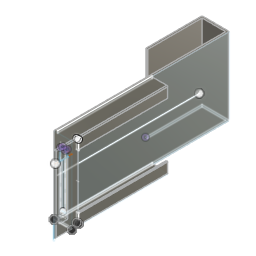
Shower Phone Caddy (Autodesk Fusion 360 design; units mm, degrees)
Autodesk Fusion 360 part; units mm, degrees
sketch "Sketch1" plane through (0, 0, 0) normal (0, 0, 1) x (1, 0, 0)
  line L0 (0, 0) -> (2, 0)
  line L1 (0, 0) -> (0, 60)
  line L2 (2, 0) -> (2, 58)
  line L3 (2, 58) -> (27, 58)
  line L4 (0, 60) -> (29, 60)
  line L5 (27, 58) -> (27, -124)
  line L6 (29, 60) -> (29, -122)
  line L7 (27, -124) -> (46, -124)
  line L8 (29, -122) -> (44, -122)
  line L9 (46, -124) -> (46, -117)
  line L10 (44, -122) -> (44, -117)
  line L11 (44, -117) -> (46, -117)
  dimension "d1" = 2
  dimension "d2" = 60
  dimension "d3" = 58
  dimension "d4" = 25
  dimension "d5" = 29
  dimension "d6" = 182
  dimension "d7" = 182
  dimension "d8" = 19
  dimension "d9" = 15
  dimension "d10" = 7
  dimension "d11" = 5
  constraint coincident L0.start L1.start
  constraint horizontal L0
  constraint perpendicular L0 L1
  constraint perpendicular L0 L2
  constraint perpendicular L2 L3
  constraint perpendicular L1 L4
  constraint perpendicular L3 L5
  constraint perpendicular L4 L6
  constraint perpendicular L5 L7
  constraint perpendicular L6 L8
  constraint perpendicular L7 L9
  constraint perpendicular L8 L10
  measures "d1" distance of L0.start L0.end
  measures "d2" distance of L0.start L1.end
  measures "d3" distance of L0.end L2.end
  measures "d4" distance of L2.end L3.end
  measures "d5" distance of L1.end L4.end
  measures "d6" distance of L3.end L5.end
  measures "d7" distance of L4.end L6.end
  measures "d8" distance of L5.end L7.end
  measures "d9" distance of L6.end L8.end
  measures "d10" distance of L7.end L9.end
  measures "d11" distance of L8.end L10.end
extrude "Extrude1" add sketch "Sketch1" along normal blind 81.5
sketch "Sketch2" plane through (29, 0, 0) normal (1, 0, 0) x (0, 1, 0)
  line L0 (-122, 0) -> (60, 0)
  line L1 (60, 0) -> (60, 81.5)
  line L2 (60, 81.5) -> (-122, 81.5)
  line L3 (-122, 81.5) -> (-122, 0)
  line L4 (-122, 0) -> (-122, 2)
  line L5 (-122, 0) -> (-22, 0)
  line L6 (-122, 2) -> (-22, 2)
  line L7 (-22, 2) -> (-22, 0)
  line L8 (-122, 40.75) -> (28, 40.75)
  line L9 (-122, 81.5) -> (-122, 79.5)
  line L10 (-122, 81.5) -> (-22, 81.5)
  line L11 (-122, 79.5) -> (-22, 79.5)
  line L12 (-22, 79.5) -> (-22, 81.5)
  dimension "d14" = 2
  dimension "d15" = 100
  dimension "d16" = 100
  dimension "d17" = 150
  constraint coincident L0.start L3.end
  constraint perpendicular L0 L4
  constraint perpendicular L3 L5
  constraint perpendicular L3 L6
  constraint midpoint L3 L8.start
  constraint perpendicular L3 L8
  constraint symmetric L0.start L8 L2.end
  constraint symmetric L4.end L8 L9.end
  constraint symmetric L5.end L8 L10.end
  constraint symmetric L6.end L8 L11.end
  measures "d14" distance of L0.start L4.end
  measures "d15" distance of L0.start L5.end
  measures "d16" distance of L4.end L6.end
  measures "d17" distance of L8.start L8.end
extrude "Extrude2" add sketch "Sketch2" along normal blind 17 contours L0 L3 L4 L5 L6 L7 | L2 L3 L9 L10 L11 L12
sketch "Sketch3" plane through (0, -117, 0) normal (0, 1, 0) x (-1, 0, 0)
  line L0 (-44, 79.5) -> (-46, 79.5)
  line L1 (-46, 79.5) -> (-46, 2)
  line L2 (-46, 2) -> (-44, 2)
  line L3 (-44, 2) -> (-44, 79.5)
  line L4 (-46, 2) -> (-46, 12)
  line L5 (-44, 2) -> (-46, 2)
  line L6 (-44, 2) -> (-44, 12)
  line L7 (-44, 12) -> (-46, 12)
  line L8 (-46, 40.75) -> (-44, 40.75) construction
  line L9 (-44, 79.5) -> (-46, 79.5)
  line L10 (-46, 79.5) -> (-46, 69.5)
  line L11 (-44, 79.5) -> (-44, 69.5)
  line L12 (-44, 69.5) -> (-46, 69.5)
  dimension "d21" = 10
  constraint coincident L1.end L2.start
  constraint perpendicular L2 L4
  constraint coincident L2.end L3.start
  constraint perpendicular L2 L6
  constraint midpoint L1 L8.start
  constraint midpoint L3 L8.end
  constraint symmetric L1.end L8 L0.end
  constraint symmetric L4.end L8 L10.end
  constraint symmetric L2.end L8 L0.start
  constraint symmetric L6.end L8 L11.end
  constraint equal L4 L6
  measures "d21" distance of L2.end L6.end
extrude "Extrude3" add sketch "Sketch3" along normal blind 95 contours L0 L1 L3 L9 L10 L11 L12 | L1 L2 L3 L4 L5 L6 L7
sketch "Sketch4" plane through (0, -124, 0) normal (0, -1, 0) x (1, 0, 0)
  line L0 (27, 0) -> (46, 0)
  line L1 (46, 0) -> (46, 81.5)
  line L2 (46, 81.5) -> (27, 81.5)
  line L3 (27, 81.5) -> (27, 0)
  line L4 (34, 74.5) -> (34, 7) construction
  line L5 (34, 7) -> (39, 7) construction
  line L6 (39, 7) -> (39, 74.5) construction
  line L7 (39, 74.5) -> (34, 74.5) construction
  line L8 (36.5, 7) -> (36.5, 12) construction
  line L9 (36.5, 74.5) -> (36.5, 69.5) construction
  line L10 (39, 69.5) -> (34, 69.5)
  line L11 (39, 12) -> (34, 12)
  line L12 (39, 69.5) -> (39, 12)
  line L13 (34, 12) -> (34, 69.5)
  dimension "d24" = -7
  dimension "d52" = 5
  constraint midpoint L5 L8.start
  constraint perpendicular L5 L8
  constraint midpoint L7 L9.start
  constraint perpendicular L7 L9
  constraint equal L8 L9
  constraint coincident L6 L10.start
  constraint coincident L4 L10.end
  constraint perpendicular L4 L10
  constraint coincident L6 L11.start
  constraint coincident L4 L11.end
  constraint perpendicular L4 L11
  measures "d52" distance of L8.start L8.end
extrude "Extrude4" cut sketch "Sketch4" against normal blind 2 contours L10 L11 L12 L13
sketch "Sketch5" plane through (0, 0, 0) normal (0, 0, -1) x (1, 0, 0)
  line L0 (46, 22) -> (46, 124)
  line L1 (46, 124) -> (27, 124)
  line L2 (27, 124) -> (27, -58)
  line L3 (27, -58) -> (2, -58)
  line L4 (2, -58) -> (2, 0)
  line L5 (2, 0) -> (0, 0)
  line L6 (0, 0) -> (0, -60)
  line L7 (0, -60) -> (29, -60)
  line L8 (29, -60) -> (29, 22)
  line L9 (29, 22) -> (46, 22)
  line L10 (27, 124) -> (46, 143)
  line L11 (46, 124) -> (46, 143)
  line L12 (46, 124) -> (27, 124)
  constraint coincident L1.end L2.start
  constraint coincident L0.end L1.start
  constraint perpendicular L1 L11
extrude "Extrude5" add sketch "Sketch5" against normal blind 81.5 contours L1 L10 L11 L12
sketch "Sketch6" plane through (0, 0, 69.5) normal (0, 0, -1) x (1, 0, 0)
  line L0 (39, 124) -> (46, 124) construction
  line L1 (46, 124) -> (46, 141.4155) construction
  line L2 (34, 124) -> (46, 137.4547)
  line L3 (46, 137.4547) -> (46, 128.4547)
  line L4 (46, 128.4547) -> (39, 124)
  line L5 (34, 122) -> (34, 124)
  line L6 (39, 122) -> (39, 124)
  line L7 (39, 122) -> (39, 122.3243)
  line L8 (39, 122) -> (34, 122)
  line L9 (39, 124) -> (34, 124)
  line L10 (34, 124) -> (34, 122)
  line L11 (34, 122) -> (39, 122)
  line L12 (39, 122) -> (39, 124)
  dimension "d31" = 9
  constraint perpendicular L0 L1
  constraint coincident L1 L2.end
  constraint parallel L1 L3
  constraint coincident L6 L7.end
  constraint perpendicular L5 L8
  measures "d31" distance of L2.end L3.end
extrude "Extrude6" cut sketch "Sketch6" along normal blind 57.5 contours L2 L3 L4 L9
fillet "Fillet1" radius 1 1 edges at (46, -143, 40.75)
fillet "Fillet1" radius 1 1 edges at (27, -124, 40.75)
fillet "Fillet1" radius 0.5 8 edges at (45, -22, 69.5) (44, -69.5, 69.5) (46, -69.5, 69.5) (46, -117, 40.75) (44, -117, 40.75) (44, -69.5, 12) (46, -69.5, 12) (45, -22, 12)
fillet "Fillet1" radius 1 2 edges at (46, -82.5, 81.5) (46, -82.5, 0)
fillet "Fillet1" radius 0.5 8 edges at (36.5, -22, 2) (44, -22, 7) (46, -22, 6) (37.5, -22, 0) (37.5, -22, 81.5) (36.5, -22, 79.5) (44, -22, 74.5) (46, -22, 75.5)
fillet "Fillet1" radius 1 2 edges at (29, 60, 40.75) (0, 60, 40.75)
fillet "Fillet1" radius 0.5 2 edges at (0, 0, 40.75) (2, 0, 40.75)
